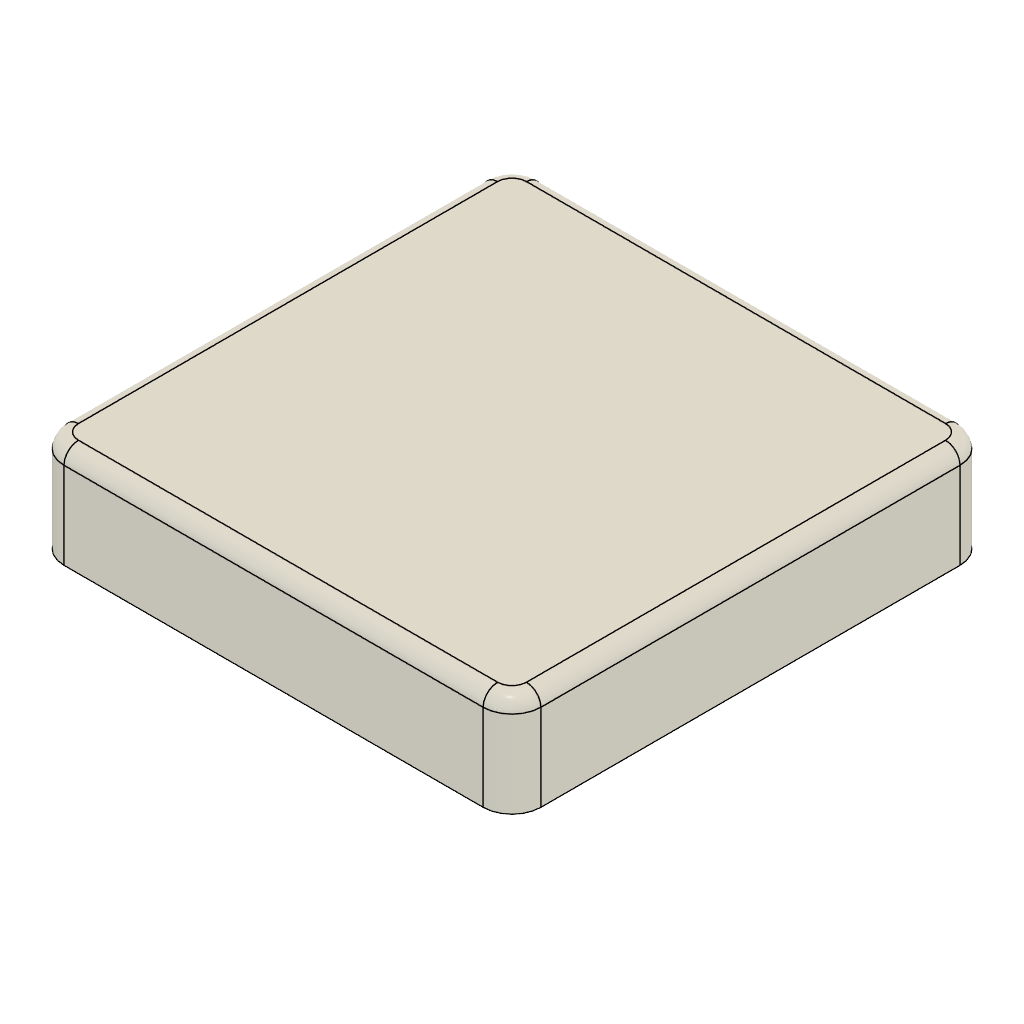
Keycap (1u) (Autodesk Fusion 360 archive; units mm, degrees)
design "Keycap (1u)" references "_Globals"
part number: 2026-10-16-12-48-24-599
Autodesk Fusion 360 part; units mm, degrees
derive "Derived from _Globals"
sketch "Sketch1" plane through (0, 0, 0) normal (0, 1, 0) x (1, 0, 0)
  line L0 (-8.25, -8.25) -> (8.25, -8.25)
  line L1 (8.25, -8.25) -> (8.25, 8.25)
  line L2 (8.25, 8.25) -> (-8.25, 8.25)
  line L3 (-8.25, 8.25) -> (-8.25, -8.25)
  line L4 (-8.25, -8.25) -> (8.25, 8.25) construction
  line L5 (8.25, -8.25) -> (-8.25, 8.25) construction
  dimension "d17" = 16.5
  dimension "d18" = 16.5
  constraint horizontal L0
  constraint perpendicular L0 L1
  constraint parallel L0 L2
  constraint parallel L1 L3
  constraint coincident L4 origin
  constraint coincident L5 origin
  measures "d17" distance of L1.end L2.end
  measures "d18" distance of L0.end L1.end
extrude "Extrude1" add sketch "Sketch1" along normal blind 3.5
fillet "Fillet1" radius 1 4 edges at (8.25, 1.75, -8.25) (-8.25, 1.75, -8.25) (-8.25, 1.75, 8.25) (8.25, 1.75, 8.25)
fillet "Fillet2" radius 0.5 8 edges at (7.9571, 3.5, -7.9571) (0, 3.5, -8.25) (-7.9571, 3.5, -7.9571) (-8.25, 3.5, 0) (-7.9571, 3.5, 7.9571) (0, 3.5, 8.25) (7.9571, 3.5, 7.9571) (8.25, 3.5, 0)
sketch "Sketch2" plane through (0, 0, 0) normal (0, -1, 0) x (1, 0, 0)
  arc A0 (8.25, 7.25) -> (7.25, 8.25) centre (7.25, 7.25) ccw
  line L0 (7.25, 8.25) -> (-7.25, 8.25)
  arc A1 (-7.25, 8.25) -> (-8.25, 7.25) centre (-7.25, 7.25) ccw
  line L1 (-8.25, 7.25) -> (-8.25, -7.25)
  arc A2 (-8.25, -7.25) -> (-7.25, -8.25) centre (-7.25, -7.25) ccw
  line L2 (-7.25, -8.25) -> (7.25, -8.25)
  arc A3 (7.25, -8.25) -> (8.25, -7.25) centre (7.25, -7.25) ccw
  line L3 (8.25, -7.25) -> (8.25, 7.25)
  line L4 (-7.25, -7.25) -> (7.25, -7.25)
  line L5 (7.25, -7.25) -> (7.25, 7.25)
  line L6 (7.25, 7.25) -> (-7.25, 7.25)
  line L7 (-7.25, 7.25) -> (-7.25, -7.25)
extrude "Extrude2" cut sketch "Sketch2" against normal blind 2.05 contours L4 L5 L6 L7
fillet "Fillet3" radius 0.5 4 edges at (-7.25, 1.025, 7.25) (7.25, 1.025, 7.25) (7.25, 1.025, -7.25) (-7.25, 1.025, -7.25)
sketch "Sketch3" plane through (0, 2.05, 0) normal (0, -1, 0) x (1, 0, 0)
  arc A0 (-7.25, -6.75) -> (-6.75, -7.25) centre (-6.75, -6.75) ccw
  line L0 (-6.75, -7.25) -> (6.75, -7.25)
  arc A1 (6.75, -7.25) -> (7.25, -6.75) centre (6.75, -6.75) ccw
  line L1 (7.25, -6.75) -> (7.25, 6.75)
  arc A2 (7.25, 6.75) -> (6.75, 7.25) centre (6.75, 6.75) ccw
  line L2 (6.75, 7.25) -> (-6.75, 7.25)
  arc A3 (-6.75, 7.25) -> (-7.25, 6.75) centre (-6.75, 6.75) ccw
  line L3 (-7.25, 6.75) -> (-7.25, -6.75)
  circle A4 centre (0, 0) radius 2.7
  line L4 (0, 0) -> (0, 2.05) construction
  line L5 (-0.7, 2.05) -> (0.7, 2.05)
  line L6 (0.7, 2.05) -> (0.7, 0.7)
  line L7 (0.7, 0.7) -> (2.05, 0.7)
  line L8 (-2.05, -0.7) -> (-2.05, 0.7)
  line L9 (-2.05, 0.7) -> (-0.7, 0.7)
  line L10 (-0.7, 0.7) -> (-0.7, 2.05)
  line L11 (0.7, -2.05) -> (-0.7, -2.05)
  line L12 (-0.7, -2.05) -> (-0.7, -0.7)
  line L13 (-0.7, -0.7) -> (-2.05, -0.7)
  line L14 (2.05, 0.7) -> (2.05, -0.7)
  line L15 (2.05, -0.7) -> (0.7, -0.7)
  line L16 (0.7, -0.7) -> (0.7, -2.05)
  dimension "d32" = 5.4
  dimension "d33" = 2.05
  dimension "d34" = 1.4
  dimension "d35" = 1.35
  dimension "d36" = 1.35
  dimension "d38" = 360
  constraint coincident A4.centre L4.start
  constraint vertical L4
  constraint horizontal L5
  constraint midpoint L4.end L5
  constraint perpendicular L5 L6
  constraint perpendicular L6 L7
  measures "d32" diameter of A4
  measures "d33" distance of A4.centre L4.end
  measures "d34" distance of L5.start L5.end
  measures "d35" distance of L5.end L6.end
  measures "d36" distance of L6.end L7.end
extrude "Extrude3" add sketch "Sketch3" along normal blind 3.35 contours A4
fillet "Fillet4" radius 0.1 1 edges at (-2.5173, -1.3, -0.9764)
fillet "Fillet5" radius 0.1 4 edges at (0.7, 0.375, -0.7) (-0.7, 0.375, -0.7) (0.7, 0.375, 0.7) (-0.7, 0.375, 0.7)
equation "keycap_size_Ref = 16.5 mm"
equation "keycap_thickness_Ref = 3.5 mm" comment "Keycap thickness without stem"
equation "keycap_full_thickness_Ref = 4.8 mm" comment "Keycap thickness from stem to top"
equation "keycap_top_fillet_Ref1 = 0.5 mm"
equation "keycap_side_fillet_Ref1 = 1 mm"
equation "stem_fillet_Ref = 0.1 mm"
equation "stem_diameter_Ref = 5.5 mm"
equation "stem_cross_length_Ref = 4 mm"
equation "stem_cross_width_Ref = 1.3 mm"
equation "stem_offset_Ref = 0.1 mm"
equation "d17 = keycap_size_Ref"
equation "d18 = keycap_size_Ref"
equation "d19 = keycap_thickness_Ref"
equation "keycap_side_width_Ref = 1 mm"
equation "d23 = keycap_side_fillet_Ref1"
equation "d25 = keycap_top_fillet_Ref1"
equation "d26 = -keycap_side_width_Ref"
equation "keycap_inner_thickness_Ref = keycap_full_thickness_Ref - 3.35 mm"
equation "d28 = -( keycap_thickness_Ref - keycap_inner_thickness_Ref )"
equation "d31 = keycap_side_fillet_Ref1 * 0.5"
equation "d32 = stem_diameter_Ref - stem_offset_Ref"
equation "d33 = ( stem_cross_length_Ref + stem_offset_Ref ) * 0.5"
equation "d34 = stem_cross_width_Ref + stem_offset_Ref"
equation "d35 = ( stem_cross_length_Ref + stem_offset_Ref ) * 0.5 - ( stem_cross_width_Ref + stem_offset_Ref ) * 0.5"
equation "d36 = ( stem_cross_length_Ref + stem_offset_Ref ) * 0.5 - ( stem_cross_width_Ref + stem_offset_Ref ) * 0.5"
equation "d39 = keycap_full_thickness_Ref - keycap_inner_thickness_Ref"
equation "d42 = stem_fillet_Ref"
equation "d44 = stem_fillet_Ref"
equation "switch_size_Ref = 19.05 mm"
named bodies: "Main"
